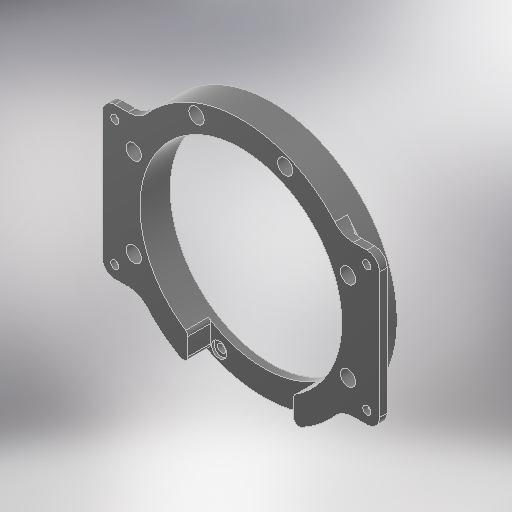
# Autodesk Inventor part: 3D_GIM-fix
Saved by Autodesk Inventor 2025.3 (Build 293356030, 356C)
## iProperties
Created: 2025-04-23
Part Number: 3D_GIM-fix
Material: 一般
Document SubType Name: Modeling
Designer: 8326d
Density: 1 g/cm^3
Appearance: 滑らか - 黒
Author: 8326d
Autodesk Inventor part; units mm, degrees
ref_plane "YZ Plane" through (0, 0, 0) normal (1, 0, 0) x (0, 1, 0)
ref_plane "XZ Plane" through (0, 0, 0) normal (0, 1, 0) x (-1, 0, 0)
ref_plane "XY Plane" through (0, 0, 0) normal (0, 0, 1) x (1, 0, 0)
sketch "スケッチ1" plane through (0, 0, 0) normal (0, 0, 1) x (1, 0, 0)
  circle A0 centre (0, 0) radius 50
  dimension "d0" = 100
  constraints: 1 centre point, 1 coincident
  measures "d0" diameter of A0
extrude "押し出し1" add sketch "スケッチ1" along normal blind 12
sketch "スケッチ2" plane through (0, 0, 12) normal (0, 0, 1) x (1, 0, 0)
  circle A0 centre (0, 0) radius 40
  dimension "d3" = 80
  constraints: 1 centre point, 1 coincident
  measures "d3" diameter of A0
extrude "押し出し2" cut sketch "スケッチ2" against normal through all
sketch "スケッチ3" plane through (0, 0, 12) normal (0, 0, 1) x (1, 0, 0)
  line L0 (0, 0) -> (42.4985, 17.6034) construction
  line L1 (0, 0) -> (46, 0) construction
  dimension "d6" = 46
  dimension "d7" = 22.5
  constraints: 4 end point, 1 coincident, 1 equal length, 1 horizontal
  measures "d6" distance of L0.start L0.end
  measures "d7" angle of L1 L0
hole "穴1" at (42.4985, 17.6034, 12) direction (0, 0, -1) diameter 3.2 end through all counterbore diameter 6 counterbore depth 10
pattern_circular "円形状パターン1" count 8 over 360 about axis through (0, 0, 12) along (0, 0, -1) of "穴1"
sketch "スケッチ4" plane through (0, 0, 12) normal (0, 0, 1) x (1, 0, 0)
  line L0 (-55, -30) -> (55, -30)
  line L1 (55, -30) -> (55, 30)
  line L2 (55, 30) -> (-55, 30)
  line L3 (-55, 30) -> (-55, -30)
  line L4 (-55, -30) -> (55, 30) construction
  line L5 (55, -30) -> (-55, 30) construction
  circle A0 centre (0, 0) radius 50 projected
  point P0 (-40, -30)
  point P1 (-40, 30)
  point P2 (40, 30)
  point P3 (40, -30)
  dimension "d18" = 110
  dimension "d19" = 60
  constraints: 12 end point, 2 midpoint, 2 parallel, 1 horizontal, 1 perpendicular
  measures "d18" distance of L2.end L1.end
  measures "d19" distance of L1.end L0.end
extrude "押し出し3" add sketch "スケッチ4" against normal blind 3 contours L3 L2 A0 L0 | A0 L2 L1 L0
sketch "スケッチ5" plane through (0, 0, 9) normal (0, 0, -1) x (-1, 0, 0)
  line L0 (50, 25) -> (-50, 25) construction
  line L1 (-50, 25) -> (-50, -25) construction
  line L2 (-50, -25) -> (50, -25) construction
  line L3 (50, -25) -> (50, 25) construction
  line L4 (50, 25) -> (-50, -25) construction
  line L5 (-50, 25) -> (50, -25) construction
  point P0 (0, 0)
  dimension "d22" = 100
  dimension "d23" = 50
  constraints: 12 end point, 2 midpoint, 2 parallel, 1 horizontal, 1 perpendicular
  measures "d22" distance of L2.end L1.end
  measures "d23" distance of L1.end L0.end
hole "穴2" at (-50, 25, 9) at (50, 25, 9) at (50, -25, 9) at (-50, -25, 9) direction (0, 0, 1) diameter 3.2 end through all counterbore diameter 6 counterbore depth 1
sketch "スケッチ6" plane through (0, 0, 0) normal (0, 1, 0) x (-1, 0, 0)
  line L0 (40, 12) -> (-40, 12) projected
  line L1 (21, 12) -> (-21, 12)
  line L2 (-21, 12) -> (-21, 3)
  line L3 (-21, 3) -> (21, 3)
  line L4 (21, 3) -> (21, 12)
  point P0 (0, 0)
  point P1 (0, 12)
  point P2 (-21, 12)
  dimension "d31" = 42
  dimension "d32" = 9
  constraints: 8 end point, 2 midpoint, 2 parallel, 1 horizontal, 1 perpendicular, 1 point on line
  measures "d31" distance of L3.end L2.end
  measures "d32" distance of L2.end L1.end
extrude "押し出し4" cut sketch "スケッチ6" against normal through all
fillet "フィレット1" radius 10 4 edges at (-40, 30, 10.5) (40, 30, 10.5) (-40, -30, 10.5) (40, -30, 10.5)
fillet "フィレット2" radius 5 4 edges at (55, -30, 10.5) (55, 30, 10.5) (-55, 30, 10.5) (-55, -30, 10.5)
chamfer "面取り1" distance 2 angle 45 7 edges at (38.6698, -31.6961, 9) (47.4342, -15.8114, 9) (47.4342, 15.8114, 9) (38.6698, 31.6961, 9) (-38.6698, -31.6961, 9) (-50, 0, 9) (-38.6698, 31.6961, 9)
fillet "フィレット3" radius 2 4 edges at (-21, -45.3762, 7.5) (-21, -34.0441, 7.5) (21, -45.3762, 7.5) (21, -34.0441, 7.5)
